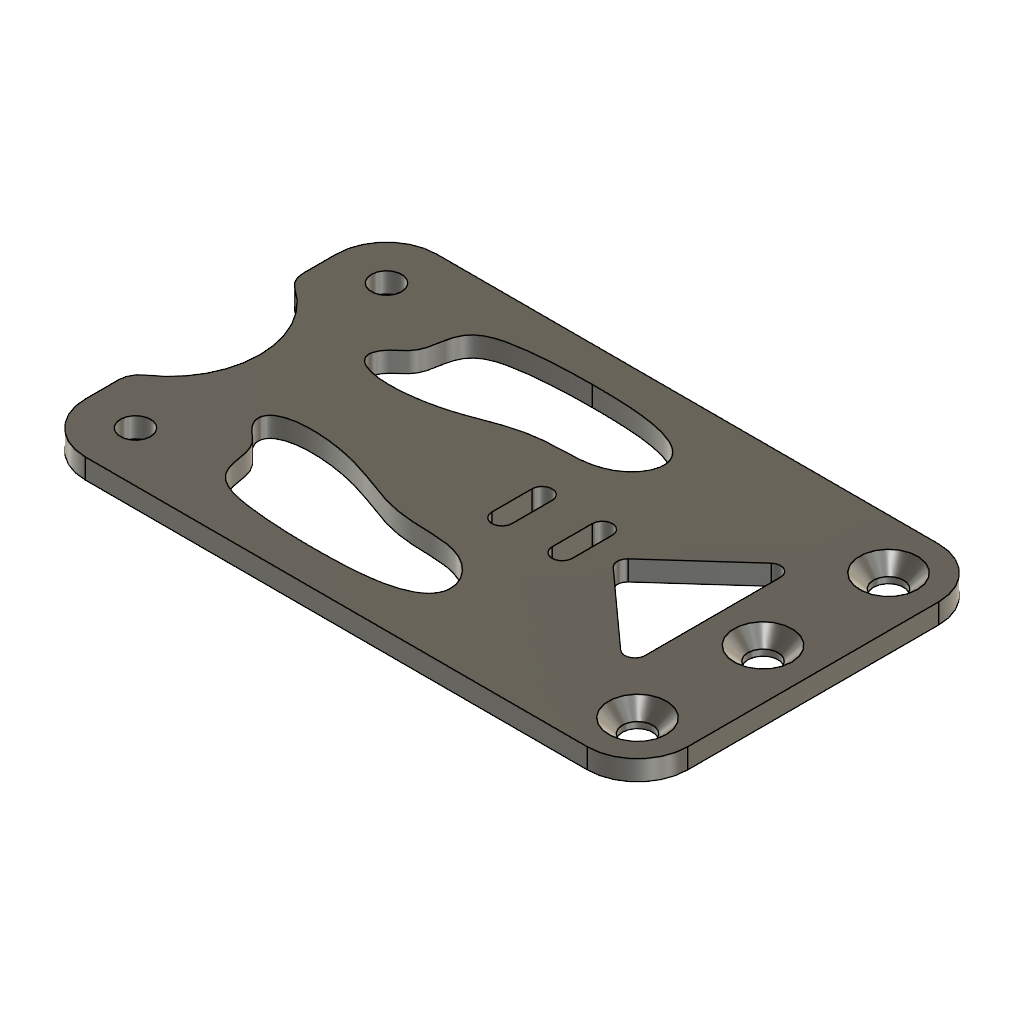
top plate (Autodesk Fusion 360 design; units mm, degrees)
part number: 2026-08-28-11-28-22-394
Autodesk Fusion 360 part; units mm, degrees
sketch "Sketch1" plane through (0, 0, 0) normal (0, 0, 1) x (1, 0, 0)
  line L0 (-30, 17.5) -> (30, 17.5)
  line L1 (30, 17.5) -> (30, -17.5)
  line L2 (30, -17.5) -> (-30, -17.5)
  line L3 (-30, -17.5) -> (-30, 17.5)
  dimension "d1" = 60
  dimension "d2" = 35
  dimension "d3" = 30
  dimension "d4" = 17.5
  constraint horizontal L0
  constraint vertical L1
  constraint horizontal L2
  constraint vertical L3
  measures "d1" distance of L1.end L2.end
  measures "d2" distance of L0 L2
  measures "d3" horizontal distance of origin L2.end
  measures "d4" vertical distance of origin L2.end
extrude "Extrude1" add sketch "Sketch1" along normal blind 2 contours L0 L1 L2 L3 picked at (-10, 5.833333)
sketch "Sketch2" plane through (0, 0, 2) normal (0, 0, 1) x (-1, 0, 0)
  line L0 (30, 17.5) -> (-30, 17.5)
  line L1 (-30, 17.5) -> (-30, -17.5)
  line L2 (-30, -17.5) -> (30, -17.5)
  line L3 (30, -17.5) -> (30, 17.5)
  point P0 (-25, -12.5)
  point P1 (-25, 0)
  point P2 (-25, 12.5)
  dimension "d7" = 25
  dimension "d8" = 12.5
  dimension "d9" = 5
  constraint vertical P0 P2
  constraint vertical P1 P2
  constraint horizontal origin P1
  measures "d7" distance of P0 P2
  measures "d8" distance of P1 P2
  measures "d9" distance of L1 P1
hole "Hole1" at (25, 12.5, 2) at (25, 0, 2) at (25, -12.5, 2) direction (0, 0, -1) diameter 3 end through all countersink diameter 5.76 countersink angle 90
sketch "Sketch3" plane through (0, 0, 2) normal (0, 0, 1) x (-1, 0, 0)
  circle A0 centre (-25, 0) radius 2.88
  circle A1 centre (-25, -12.5) radius 2.88
  circle A2 centre (-25, 12.5) radius 2.88
  line L0 (30, 17.5) -> (-30, 17.5)
  line L1 (-30, 17.5) -> (-30, -17.5)
  line L2 (-30, -17.5) -> (30, -17.5)
  line L3 (30, -17.5) -> (30, 17.5)
  point P0 (25, -12.5)
  point P1 (25, 12.5)
  dimension "d14" = 5
  constraint vertical P0 P1
  constraint horizontal A2.centre P1
  constraint horizontal A1.centre P0
  measures "d14" distance of L3 P0
hole "Hole2" at (-25, 12.5, 2) at (-25, -12.5, 2) direction (0, 0, -1) diameter 3 end through all
fillet "Fillet1" radius 5 4 edges at (-30, -17.5, 1) (-30, 17.5, 1) (30, -17.5, 1) (30, 17.5, 1)
sketch "Sketch4" plane through (0, 0, 2) normal (0, 0, 1) x (-1, 0, 0)
  circle A0 centre (25, -12.5) radius 1.5
  circle A1 centre (25, 12.5) radius 1.5
  circle A2 centre (-25, 0) radius 2.88
  circle A3 centre (-25, -12.5) radius 2.88
  circle A4 centre (-25, 12.5) radius 2.88
  arc A5 (-30, -12.5) -> (-25, -17.5) centre (-25, -12.5) ccw
  line L0 (-25, -17.5) -> (25, -17.5)
  arc A6 (25, -17.5) -> (30, -12.5) centre (25, -12.5) ccw
  line L1 (30, -12.5) -> (30, 12.5)
  arc A7 (30, 12.5) -> (25, 17.5) centre (25, 12.5) ccw
  line L2 (25, 17.5) -> (-25, 17.5)
  arc A8 (-25, 17.5) -> (-30, 12.5) centre (-25, 12.5) ccw
  line L3 (-30, 12.5) -> (-30, -12.5)
  line L4 (0, 2) -> (0, -2)
  arc A9 (-2, -2) -> (0, -2) centre (-1, -2) ccw
  line L5 (-2, -2) -> (-2, 2)
  arc A10 (0, 2) -> (-2, 2) centre (-1, 2) ccw
  line L6 (-8, -2) -> (-8, 2)
  arc A11 (-6, 2) -> (-8, 2) centre (-7, 2) ccw
  line L7 (-6, 2) -> (-6, -2)
  arc A12 (-8, -2) -> (-6, -2) centre (-7, -2) ccw
  dimension "d19" = 2
  dimension "d20" = 2
  dimension "d21" = 6
  dimension "d22" = 4
  dimension "d23" = 2
  dimension "d24" = 23
  constraint vertical L4
  constraint tangent L4 A9
  constraint tangent A9 L5
  constraint parallel L4 L5
  constraint tangent L5 A10
  constraint tangent L4 A10
  constraint vertical L7
  constraint tangent L7 A12
  constraint tangent L6 A12
  constraint parallel L6 L7
  constraint tangent L6 A11
  constraint tangent A11 L7
  constraint horizontal A10.centre A11.centre
  constraint horizontal A9.centre A12.centre
  measures "d19" distance of L4 L5
  measures "d20" distance of L6 L7
  measures "d21" distance of A10.centre A11.centre
  measures "d22" distance of A12.centre A11.centre
  measures "d23" vertical distance of origin A10.centre
  measures "d24" distance of L3 A11.centre
extrude "Extrude2" cut sketch "Sketch4" against normal blind 2 contours L4 A9 L5 A10 | L6 A11 L7 A12 picked at (-0.666667, -0.666667) picked at (-6.666667, -0.666667)
sketch "Sketch5" plane through (0, 0, 2) normal (0, 0, 1) x (-1, 0, 0)
  arc A0 (-30, -12.5) -> (-25, -17.5) centre (-25, -12.5) ccw
  line L0 (-25, -17.5) -> (25, -17.5)
  arc A1 (25, -17.5) -> (30, -12.5) centre (25, -12.5) ccw
  line L1 (30, -12.5) -> (30, 12.5)
  arc A2 (30, 12.5) -> (25, 17.5) centre (25, 12.5) ccw
  line L2 (25, 17.5) -> (-25, 17.5)
  arc A3 (-25, 17.5) -> (-30, 12.5) centre (-25, 12.5) ccw
  line L3 (-30, 12.5) -> (-30, -12.5)
  circle A4 centre (-25, 12.5) radius 2.88
  circle A5 centre (-25, -12.5) radius 2.88
  circle A6 centre (-25, 0) radius 2.88
  circle A7 centre (25, 12.5) radius 1.5
  circle A8 centre (25, -12.5) radius 1.5
  line L4 (-8, -2) -> (-8, 2)
  arc A9 (-6, 2) -> (-8, 2) centre (-7, 2) ccw
  line L5 (-6, 2) -> (-6, -2)
  arc A10 (-8, -2) -> (-6, -2) centre (-7, -2) ccw
  line L6 (0, 2) -> (0, -2)
  arc A11 (-2, -2) -> (0, -2) centre (-1, -2) ccw
  line L7 (-2, -2) -> (-2, 2)
  arc A12 (0, 2) -> (-2, 2) centre (-1, 2) ccw
  line L8 (-20, 9) -> (-10, 0)
  line L9 (-10, 0) -> (-20, -9)
  line L10 (-20, -9) -> (-20, 9)
  dimension "d27" = 18
  dimension "d28" = 9
  dimension "d29" = 2
  dimension "d30" = 5
  constraint vertical L10
  constraint horizontal A6.centre L8.end
  measures "d27" distance of L8.start L9.end
  measures "d28" vertical distance of L8.start L8.end
  measures "d29" distance of L4 L8.end
  measures "d30" distance of A6.centre L10
extrude "Extrude3" cut sketch "Sketch5" against normal blind 2 contours L8 L9 L10 picked at (-16.666667, 0)
fillet "Fillet2" radius 1 3 edges at (20, 9, 1) (10, 0, 1) (20, -9, 1)
sketch "Sketch6" plane through (0, 0, 2) normal (0, 0, 1) x (-1, 0, 0)
  line L0 (0, 2) -> (0, -2)
  arc A0 (-2, -2) -> (0, -2) centre (-1, -2) ccw
  line L1 (-2, -2) -> (-2, 2)
  arc A1 (0, 2) -> (-2, 2) centre (-1, 2) ccw
  line L2 (-8, -2) -> (-8, 2)
  arc A2 (-6, 2) -> (-8, 2) centre (-7, 2) ccw
  line L3 (-6, 2) -> (-6, -2)
  arc A3 (-8, -2) -> (-6, -2) centre (-7, -2) ccw
  circle A4 centre (25, -12.5) radius 1.5
  circle A5 centre (25, 12.5) radius 1.5
  circle A6 centre (-25, 0) radius 2.88
  circle A7 centre (-25, -12.5) radius 2.88
  circle A8 centre (-25, 12.5) radius 2.88
  arc A9 (-30, -12.5) -> (-25, -17.5) centre (-25, -12.5) ccw
  line L4 (-25, -17.5) -> (25, -17.5)
  arc A10 (25, -17.5) -> (30, -12.5) centre (25, -12.5) ccw
  line L5 (30, -12.5) -> (30, 12.5)
  arc A11 (30, 12.5) -> (25, 17.5) centre (25, 12.5) ccw
  line L6 (25, 17.5) -> (-25, 17.5)
  arc A12 (-25, 17.5) -> (-30, 12.5) centre (-25, 12.5) ccw
  line L7 (-30, 12.5) -> (-30, -12.5)
  line L8 (-18.331035, 7.497932) -> (-10.825882, 0.743294)
  arc A13 (-10.825882, -0.743294) -> (-10.825882, 0.743294) centre (-11.494847, 0) ccw
  line L9 (-10.825882, -0.743294) -> (-18.331035, -7.497932)
  arc A14 (-20, -6.754638) -> (-18.331035, -7.497932) centre (-19, -6.754638) ccw
  line L10 (-20, -6.754638) -> (-20, 6.754638)
  arc A15 (-18.331035, 7.497932) -> (-20, 6.754638) centre (-19, 6.754638) ccw
  spline S0 degree 5 poles (18.380032, 7.470408) (18.508831, 7.354913) (18.77546, 7.128382) (19.181173, 6.784257) (19.624796, 6.24706) (19.853273, 5.512207) (19.639438, 4.826201) (18.966235, 4.297472) (17.899583, 3.963879) (16.558455, 3.828061) (15.084144, 3.862596) (13.611643, 4.027068) (12.236621, 4.281257) (10.995215, 4.59591) (9.883195, 4.947788) (8.86805, 5.317825) (7.904124, 5.687831) (6.94558, 6.038335) (5.962404, 6.344609) (4.940277, 6.582654) (3.876158, 6.737723) (2.77522, 6.81234) (1.647499, 6.833834) (0.504023, 6.864122) (-0.638288, 6.982513) (-1.751039, 7.266083) (-2.788313, 7.769913) (-3.682341, 8.509644) (-4.334343, 9.43699) (-4.63343, 10.45589) (-4.4867, 11.45368) (-3.842937, 12.325344) (-2.725459, 13.005044) (-1.23989, 13.479891) (0.46534, 13.77111) (2.228719, 13.922102) (3.908228, 13.984114) (5.415003, 14.002308) (6.741154, 14.003243) (8.00784, 13.976751) (9.272387, 13.922197) (10.560388, 13.837678) (11.862231, 13.718377) (13.142468, 13.550878) (14.344661, 13.310565) (15.39556, 12.954121) (16.223805, 12.433521) (16.787322, 11.719936) (17.095905, 10.823716) (17.240718, 9.818126) (17.404226, 8.852016) (17.678232, 8.205604) (18.002665, 7.821352) (18.251232, 7.585904) (18.380032, 7.470408) knots 0 0 0 0 0 0 0.02 0.04 0.06 0.08 0.1 0.12 0.14 0.16 0.18 0.2 0.22 0.24 0.26 0.28 0.3 0.32 0.34 0.36 0.38 0.4 0.42 0.44 0.46 0.48 0.5 0.52 0.54 0.56 0.58 0.6 0.62 0.64 0.66 0.68 0.7 0.72 0.74 0.76 0.78 0.8 0.82 0.84 0.86 0.88 0.9 0.92 0.94 0.96 0.98 1 1 1 1 1 1
  line L11 (3, 14) -> (9, 14)
  line L12 (-1.75, 0) -> (-22.5, 0)
  spline S1 degree 5 poles (18.380032, -7.470408) (18.508831, -7.354913) (18.77546, -7.128382) (19.181173, -6.784257) (19.624796, -6.24706) (19.853273, -5.512207) (19.639438, -4.826201) (18.966235, -4.297472) (17.899583, -3.963879) (16.558455, -3.828061) (15.084144, -3.862596) (13.611643, -4.027068) (12.236621, -4.281257) (10.995215, -4.59591) (9.883195, -4.947788) (8.86805, -5.317825) (7.904124, -5.687831) (6.94558, -6.038335) (5.962404, -6.344609) (4.940277, -6.582654) (3.876158, -6.737723) (2.77522, -6.81234) (1.647499, -6.833834) (0.504023, -6.864122) (-0.638288, -6.982513) (-1.751039, -7.266083) (-2.788313, -7.769913) (-3.682341, -8.509644) (-4.334343, -9.43699) (-4.63343, -10.45589) (-4.4867, -11.45368) (-3.842937, -12.325344) (-2.725459, -13.005044) (-1.23989, -13.479891) (0.46534, -13.77111) (2.228719, -13.922102) (3.908228, -13.984114) (5.415003, -14.002308) (6.741154, -14.003243) (8.00784, -13.976751) (9.272387, -13.922197) (10.560388, -13.837678) (11.862231, -13.718377) (13.142468, -13.550878) (14.344661, -13.310565) (15.39556, -12.954121) (16.223805, -12.433521) (16.787322, -11.719936) (17.095905, -10.823716) (17.240718, -9.818126) (17.404226, -8.852016) (17.678232, -8.205604) (18.002665, -7.821352) (18.251232, -7.585904) (18.380032, -7.470408) knots 0 0 0 0 0 0 0.02 0.04 0.06 0.08 0.1 0.12 0.14 0.16 0.18 0.2 0.22 0.24 0.26 0.28 0.3 0.32 0.34 0.36 0.38 0.4 0.42 0.44 0.46 0.48 0.5 0.52 0.54 0.56 0.58 0.6 0.62 0.64 0.66 0.68 0.7 0.72 0.74 0.76 0.78 0.8 0.82 0.84 0.86 0.88 0.9 0.92 0.94 0.96 0.98 1 1 1 1 1 1
  line L13 (15.765908, 9.814509) -> (20.994155, 5.126308)
  line L14 (15.765908, -9.814509) -> (20.994155, -5.126308)
  line L15 (3, -14) -> (9, -14)
  line L16 (3, -14) -> (9, -14)
  point P0 (19.670054, 5.126308)
  point P1 (14, 4)
  point P2 (7.685327, 5.764249)
  point P3 (2.650077, 6.80459)
  point P4 (-3, 8)
  point P5 (-4, 12)
  point P6 (6, 14)
  point P7 (13.511236, 13.462772)
  point P8 (17, 11)
  point P9 (-3, -8)
  point P10 (17, -11)
  point P11 (-4, -12)
  point P12 (19.670054, -5.126308)
  point P13 (2.650077, -6.80459)
  point P14 (13.511236, -13.462772)
  point P15 (7.685327, -5.764249)
  point P16 (14, -4)
  point P17 (6, -14)
  constraint midpoint P6 L11
  constraint symmetric P1 L12 P16
  constraint symmetric P4 L12 P9
  constraint symmetric P5 L12 P11
  constraint symmetric P6 L12 P17
  constraint symmetric P8 L12 P10
  constraint symmetric L11.start L12 L15.start
  constraint symmetric L11.end L12 L15.end
extrude "Extrude4" cut sketch "Sketch6" against normal blind 2 contours S0 L13 | S0 L13 | S1 L14 | S1 L14 picked at (8.380911, 11.233696) picked at (18.784558, 7.110333) picked at (18.784558, -7.110333) picked at (8.380911, -11.233696)
sketch "Sketch7" plane through (0, 0, 2) normal (0, 0, 1) x (-1, 0, 0)
  line L0 (-18.331035, 7.497932) -> (-10.825882, 0.743294)
  arc A0 (-10.825882, -0.743294) -> (-10.825882, 0.743294) centre (-11.494847, 0) ccw
  line L1 (-10.825882, -0.743294) -> (-18.331035, -7.497932)
  arc A1 (-20, -6.754638) -> (-18.331035, -7.497932) centre (-19, -6.754638) ccw
  line L2 (-20, -6.754638) -> (-20, 6.754638)
  arc A2 (-18.331035, 7.497932) -> (-20, 6.754638) centre (-19, 6.754638) ccw
  arc A3 (-30, -12.5) -> (-25, -17.5) centre (-25, -12.5) ccw
  line L3 (-25, -17.5) -> (25, -17.5)
  arc A4 (25, -17.5) -> (30, -12.5) centre (25, -12.5) ccw
  line L4 (30, -12.5) -> (30, 12.5)
  arc A5 (30, 12.5) -> (25, 17.5) centre (25, 12.5) ccw
  line L5 (25, 17.5) -> (-25, 17.5)
  arc A6 (-25, 17.5) -> (-30, 12.5) centre (-25, 12.5) ccw
  line L6 (-30, 12.5) -> (-30, -12.5)
  circle A7 centre (-25, 12.5) radius 2.88
  circle A8 centre (-25, -12.5) radius 2.88
  circle A9 centre (-25, 0) radius 2.88
  circle A10 centre (25, 12.5) radius 1.5
  circle A11 centre (25, -12.5) radius 1.5
  line L7 (-8, -2) -> (-8, 2)
  arc A12 (-6, 2) -> (-8, 2) centre (-7, 2) ccw
  line L8 (-6, 2) -> (-6, -2)
  arc A13 (-8, -2) -> (-6, -2) centre (-7, -2) ccw
  line L9 (0, 2) -> (0, -2)
  arc A14 (-2, -2) -> (0, -2) centre (-1, -2) ccw
  line L10 (-2, -2) -> (-2, 2)
  arc A15 (0, 2) -> (-2, 2) centre (-1, 2) ccw
  spline S0 degree 5 poles (18.380032, 7.470408) (18.508831, 7.354913) (18.77546, 7.128382) (19.181173, 6.784257) (19.624796, 6.24706) (19.853273, 5.512207) (19.639438, 4.826201) (18.966235, 4.297472) (17.899583, 3.963879) (16.558455, 3.828061) (15.084144, 3.862596) (13.611643, 4.027068) (12.236621, 4.281257) (10.995215, 4.59591) (9.883195, 4.947788) (8.86805, 5.317825) (7.904124, 5.687831) (6.94558, 6.038335) (5.962404, 6.344609) (4.940277, 6.582654) (3.876158, 6.737723) (2.77522, 6.81234) (1.647499, 6.833834) (0.504023, 6.864122) (-0.638288, 6.982513) (-1.751039, 7.266083) (-2.788313, 7.769913) (-3.682341, 8.509644) (-4.334343, 9.43699) (-4.63343, 10.45589) (-4.4867, 11.45368) (-3.842937, 12.325344) (-2.725459, 13.005044) (-1.23989, 13.479891) (0.46534, 13.77111) (2.228719, 13.922102) (3.908228, 13.984114) (5.415003, 14.002308) (6.741154, 14.003243) (8.00784, 13.976751) (9.272387, 13.922197) (10.560388, 13.837678) (11.862231, 13.718377) (13.142468, 13.550878) (14.344661, 13.310565) (15.39556, 12.954121) (16.223805, 12.433521) (16.787322, 11.719936) (17.095905, 10.823716) (17.240718, 9.818126) (17.404226, 8.852016) (17.678232, 8.205604) (18.002665, 7.821352) (18.251232, 7.585904) (18.380032, 7.470408) knots 0 0 0 0 0 0 0.02 0.04 0.06 0.08 0.1 0.12 0.14 0.16 0.18 0.2 0.22 0.24 0.26 0.28 0.3 0.32 0.34 0.36 0.38 0.4 0.42 0.44 0.46 0.48 0.5 0.52 0.54 0.56 0.58 0.6 0.62 0.64 0.66 0.68 0.7 0.72 0.74 0.76 0.78 0.8 0.82 0.84 0.86 0.88 0.9 0.92 0.94 0.96 0.98 1 1 1 1 1 1
  spline S1 degree 5 poles (6, -14) (5.876992, -14) (5.47862, -13.999252) (4.781623, -13.994037) (3.724622, -13.977335) (2.228719, -13.922102) (0.46534, -13.77111) (-1.23989, -13.479891) (-2.725459, -13.005044) (-3.842937, -12.325344) (-4.4867, -11.45368) (-4.63343, -10.45589) (-4.334343, -9.43699) (-3.682341, -8.509644) (-2.788313, -7.769913) (-1.751039, -7.266083) (-0.638288, -6.982513) (0.504023, -6.864122) (1.647499, -6.833834) (2.77522, -6.81234) (3.876158, -6.737723) (4.940277, -6.582654) (5.962404, -6.344609) (6.94558, -6.038335) (7.904124, -5.687831) (8.86805, -5.317825) (9.883195, -4.947788) (10.995215, -4.59591) (12.236621, -4.281257) (13.611643, -4.027068) (15.084144, -3.862596) (16.558455, -3.828061) (17.899583, -3.963879) (18.966235, -4.297472) (19.639438, -4.826201) (19.853273, -5.512207) (19.624796, -6.24706) (19.181173, -6.784257) (18.77546, -7.128382) (18.508831, -7.354913) (18.380032, -7.470408) (18.251232, -7.585904) (18.002665, -7.821352) (17.678232, -8.205604) (17.404226, -8.852016) (17.240718, -9.818126) (17.095905, -10.823716) (16.787322, -11.719936) (16.223805, -12.433521) (15.39556, -12.954121) (14.344661, -13.310565) (13.142468, -13.550878) (11.862231, -13.718377) (10.560388, -13.837678) (9.272387, -13.922197) (8.122508, -13.971804) (7.224193, -13.992851) (6.562693, -13.99904) (6.148297, -14) (6, -14) knots -0.70906788 -0.70906788 -0.70906788 -0.70906788 -0.70906788 -0.70906788 -0.7 -0.68 -0.66 -0.64 -0.62 -0.6 -0.58 -0.56 -0.54 -0.52 -0.5 -0.48 -0.46 -0.44 -0.42 -0.4 -0.38 -0.36 -0.34 -0.32 -0.3 -0.28 -0.26 -0.24 -0.22 -0.2 -0.18 -0.16 -0.14 -0.12 -0.1 -0.08 -0.06 -0.04 -0.02 0 0 0 0 0 0.02 0.04 0.06 0.08 0.1 0.12 0.14 0.16 0.18 0.2 0.22 0.24 0.26 0.28 0.29093212 0.29093212 0.29093212 0.29093212 0.29093212 0.29093212
  arc A16 (30, 8) -> (30, -8) centre (34.123106, 0) ccw
  line L11 (30, -12.5) -> (30, 12.5)
  dimension "d37" = 16
  dimension "d38" = 4.5
  dimension "d39" = 9
  constraint coincident L4 A16.start
  constraint coincident L4 A16.end
  measures "d37" distance of A16.end A16.start
  measures "d38" vertical distance of A5.centre A16.start
  measures "d39" radius of A16
extrude "Extrude5" cut sketch "Sketch7" against normal blind 4 contours L4 A16 L11 picked at (28.38424, 1.695341)
fillet "Fillet3" radius 2 2 edges at (-30, 8, 1) (-30, -8, 1)
equation "d8 = ( 25 / 2 ) * 1 mm"
equation "d38 = ( ( 25 - 16 ) / 2 ) * 1 mm"
